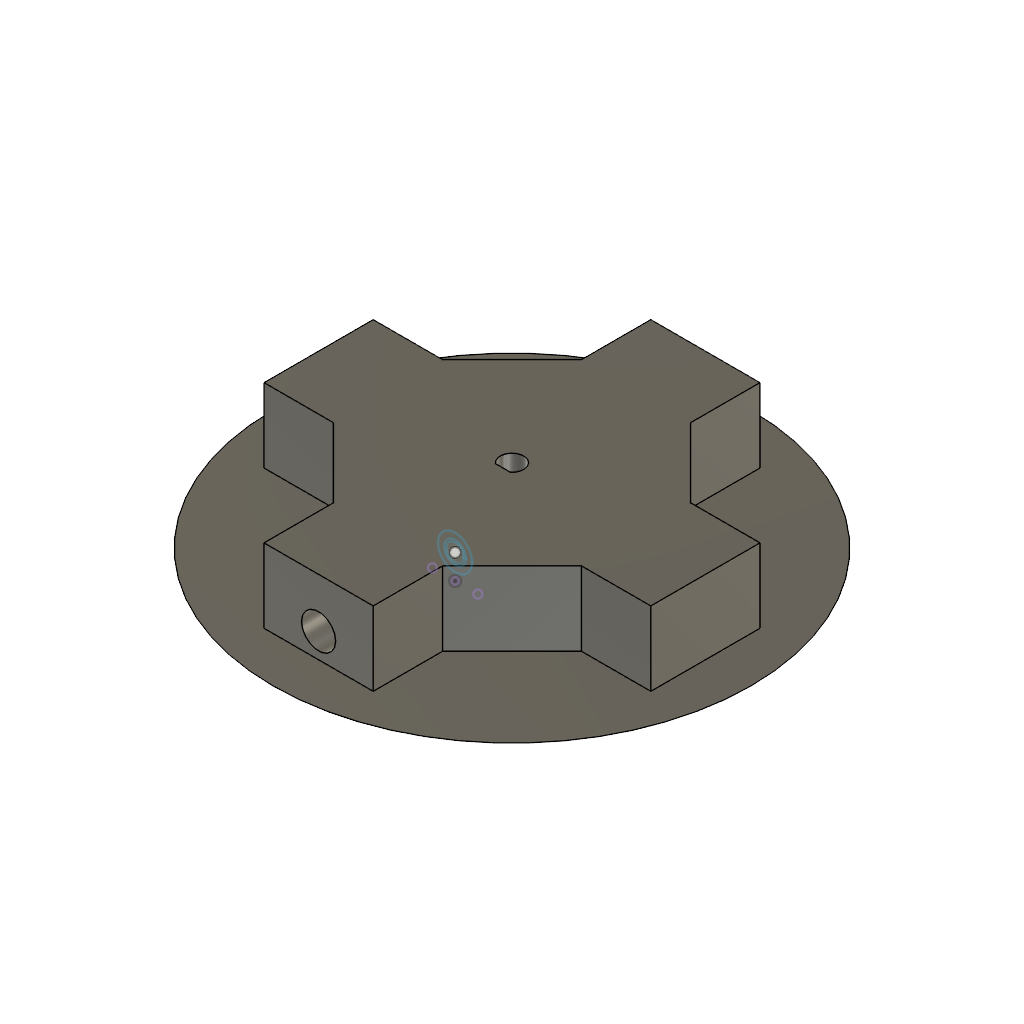
Wheels-CR-1 (Autodesk Fusion 360 design; units mm, degrees)
part number: 2026-09-08-19-14-39-740
Autodesk Fusion 360 part; units mm, degrees
sketch "Sketch1" plane through (0, 0, 0) normal (0, 0, 1) x (1, 0, 0)
  circle A0 centre (0, 0) radius 17.5
  dimension "d1" = 35
  constraint coincident A0.centre origin
  measures "d1" diameter of A0
sketch "Sketch2" plane through (0, 0, 0) normal (0, 0, 1) x (1, 0, 0)
  circle A0 centre (0, 0) radius 2.0625
  line L0 (-1.3125, -1.591) -> (1.3125, -1.591)
  line L1 (-4, 10) -> (4, 10)
  line L2 (4, 10) -> (4, -10)
  line L3 (4, -10) -> (-4, -10)
  line L4 (-4, -10) -> (-4, 10)
  line L5 (-10, 4) -> (10, 4)
  line L6 (10, 4) -> (10, -4)
  line L7 (10, -4) -> (-10, -4)
  line L8 (-10, -4) -> (-10, 4)
  dimension "d2" = 4.125
  dimension "d4" = 2.625
  dimension "d5" = 8
  dimension "d6" = 20
  dimension "d7" = 10
  dimension "d8" = 4
  dimension "d9" = 20
  dimension "d10" = 8
  dimension "d11" = 10
  dimension "d12" = 4
  constraint coincident A0.centre origin
  constraint coincident A0 L0.start
  constraint coincident A0 L0.end
  constraint horizontal L0
  constraint horizontal L1
  constraint vertical L2
  constraint horizontal L3
  constraint vertical L4
  constraint horizontal L5
  constraint vertical L6
  constraint horizontal L7
  constraint vertical L8
  measures "d2" diameter of A0
  measures "d4" distance of L0.start L0.end
  measures "d5" distance of L1.start L1.end
  measures "d6" distance of L1.start L3.end
  measures "d7" distance of A0.centre L1
  measures "d8" distance of A0.centre L2
  measures "d9" distance of L5.start L5.end
  measures "d10" distance of L5.start L7.end
  measures "d11" distance of A0.centre L8
  measures "d12" distance of A0.centre L5
extrude "Extrude1" add sketch "Sketch2" along normal blind 13 contours A0 L0 | L1 L2 L4 L5 | L2 L4 L5 L7 | L4 L5 L7 L8 | L2 L5 L6 L7 | L2 L3 L4 L7 picked at (-0.3604, -1.6461)
extrude "Extrude2" add sketch "Sketch1" against normal blind 2
chamfer "Chamfer1" distance 2 angle 45 1 edges at (-16.3157, 6.3283, -2) tangent chain off
sketch "Sketch3" plane through (0, -10, 0) normal (0, -1, 0) x (1, 0, 0)
  line L0 (4, 0) -> (4, 13)
  line L1 (4, 13) -> (-4, 13)
  line L2 (-4, 13) -> (-4, 0)
  circle A0 centre (0, 4.3395) radius 1.495
  circle A1 centre (0, 4.3395) radius 1.9024
  circle A2 centre (0, 4.3395) radius 3
  dimension "d18" = 2.99
  dimension "d42" = 3.8049
  dimension "d43" = 6
  constraint concentric A0 A1
  constraint concentric A1 A2
  constraint vertical origin A0.centre
  measures "d18" diameter of A0
  measures "d42" diameter of A1
  measures "d43" diameter of A2
sketch "Sketch4" plane through (0, 0, 13) normal (0, 0, 1) x (-1, 0, 0)
  line L0 (-1.3125, 1.591) -> (1.3125, 1.591)
  arc A0 (-1.3125, 1.591) -> (1.3125, 1.591) centre (0, 0) ccw
  line L1 (10, 4) -> (4, 4)
  line L2 (4, 4) -> (4, 10)
  line L3 (4, 10) -> (-4, 10)
  line L4 (-4, 10) -> (-4, 4)
  line L5 (-4, 4) -> (-10, 4)
  line L6 (-10, 4) -> (-10, -4)
  line L7 (-10, -4) -> (-4, -4)
  line L8 (-4, -4) -> (-4, -10)
  line L9 (-4, -10) -> (4, -10)
  line L10 (4, -10) -> (4, -4)
  line L11 (4, -4) -> (10, -4)
  line L12 (10, -4) -> (10, 4)
  line L13 (4, -10) -> (-4, -10)
  line L14 (-4, -10) -> (-4, 10)
  line L15 (-4, 10) -> (4, 10)
  line L16 (4, 10) -> (4, -10)
  line L17 (10, -4) -> (-10, -4)
  line L18 (-10, -4) -> (-10, 4)
  line L19 (-10, 4) -> (10, 4)
  line L20 (10, 4) -> (10, -4)
  circle A1 centre (0, 0) radius 18
  circle A2 centre (0, 0) radius 10.7703
  dimension "d21" = 36
  constraint horizontal L13
  constraint vertical L14
  constraint horizontal L15
  constraint vertical L16
  constraint coincident L3.end L4.start
  constraint coincident L9.end L10.start
  constraint horizontal L17
  constraint vertical L18
  constraint horizontal L19
  constraint vertical L20
  constraint coincident L5.end L6.start
  constraint coincident L11.end L12.start
  constraint coincident A0.centre A1.centre
  constraint coincident L5.end A2
  measures "d21" diameter of A1
scale "Scale1" factors (2.4, 2.4, 1) about (-17.5, 0, 0) bodies 1
move_body "Move1" bodies 1 to x (1, 0, 0) y (0, 1, 0) z (0, 0, 1) at (-25, 0, 0)
move_body "Move2" bodies 1 to x (1, 0, 0) y (0, 1, 0) z (0, 0, 1) at (0.5, 0, 0)
extrude "Extrude4" add sketch "Sketch4" along normal up to surface contours L1 L11 L12 L16 L17 L19 L20 | L12 L20 A2 | L1 L2 L16 L19 A2 | L2 L3 L4 L14 L15 L16 L19 | L14 L16 L17 L19 | L10 L11 L16 L17 A2 | L8 L9 L10 L13 L14 L16 L17 | L4 L5 L14 L19 A2 | L5 L6 L7 L14 L17 L18 L19 | L9 L13 A2 | L7 L8 L14 L17 A2 end surface at (-9.3068, -9.0593, -2)
extrude "Extrude5" cut sketch "Sketch3" along normal up to surface contours A0 | A1 | A2 end surface at (-3.2, -24, 8.6667)
extrude "Extrude6" add 1 faces at (3.2, 24, 8.6667) along direction (0, 1, 0) blind 10
extrude "Extrude7" add 1 faces at (-24, 3.2, 8.6667) along direction (-1, 0, 0) blind 10
extrude "Extrude11" cut sketch "Sketch3" against normal blind 10 contours A0 | A1
extrude "Extrude8" add 1 faces at (24, -3.2, 8.6667) along direction (1, 0, 0) blind 10
extrude "Extrude9" add 1 faces at (7.3607, -24, 6.0573) along direction (0, -1, 0) blind 10
sketch "Sketch5" plane through (0, 0, 13) normal (0, 0, 1) x (-1, 0, 0)
  arc A0 (-1.3125, 1.591) -> (1.3125, 1.591) centre (0, 0) ccw
  line L0 (-1.3125, 1.591) -> (1.3125, 1.591)
  line L1 (34, 9.6) -> (9.6, 9.6)
  line L2 (9.6, 9.6) -> (9.6, 34)
  line L3 (9.6, 34) -> (-9.6, 34)
  line L4 (-9.6, 34) -> (-9.6, 9.6)
  line L5 (-9.6, 9.6) -> (-34, 9.6)
  line L6 (-34, 9.6) -> (-34, -9.6)
  line L7 (-34, -9.6) -> (-9.6, -9.6)
  line L8 (-9.6, -9.6) -> (-9.6, -34)
  line L9 (-9.6, -34) -> (9.6, -34)
  line L10 (9.6, -34) -> (9.6, -9.6)
  line L11 (9.6, -9.6) -> (34, -9.6)
  line L12 (34, -9.6) -> (34, 9.6)
  line L13 (-9.6, 21.8) -> (-21.8, 9.6)
  line L14 (-21.8, -9.6) -> (-9.6, -21.8)
  line L15 (9.6, -21.8) -> (21.8, -9.6)
  line L16 (21.8, 9.6) -> (9.6, 21.8)
  dimension "d38" = 360
  constraint midpoint L4 L13.start
  constraint midpoint L5 L13.end
extrude "Extrude10" add sketch "Sketch5" along normal up to surface contours L1 L2 L16 | L10 L11 L15 | L4 L5 L13 | L7 L8 L14 end surface at (-15.6062, -25.0807, 0)
equation "d2 = ( 2.75 mm ) * 1.5"
equation "d4 = ( 1.75 mm ) * 1.5"
